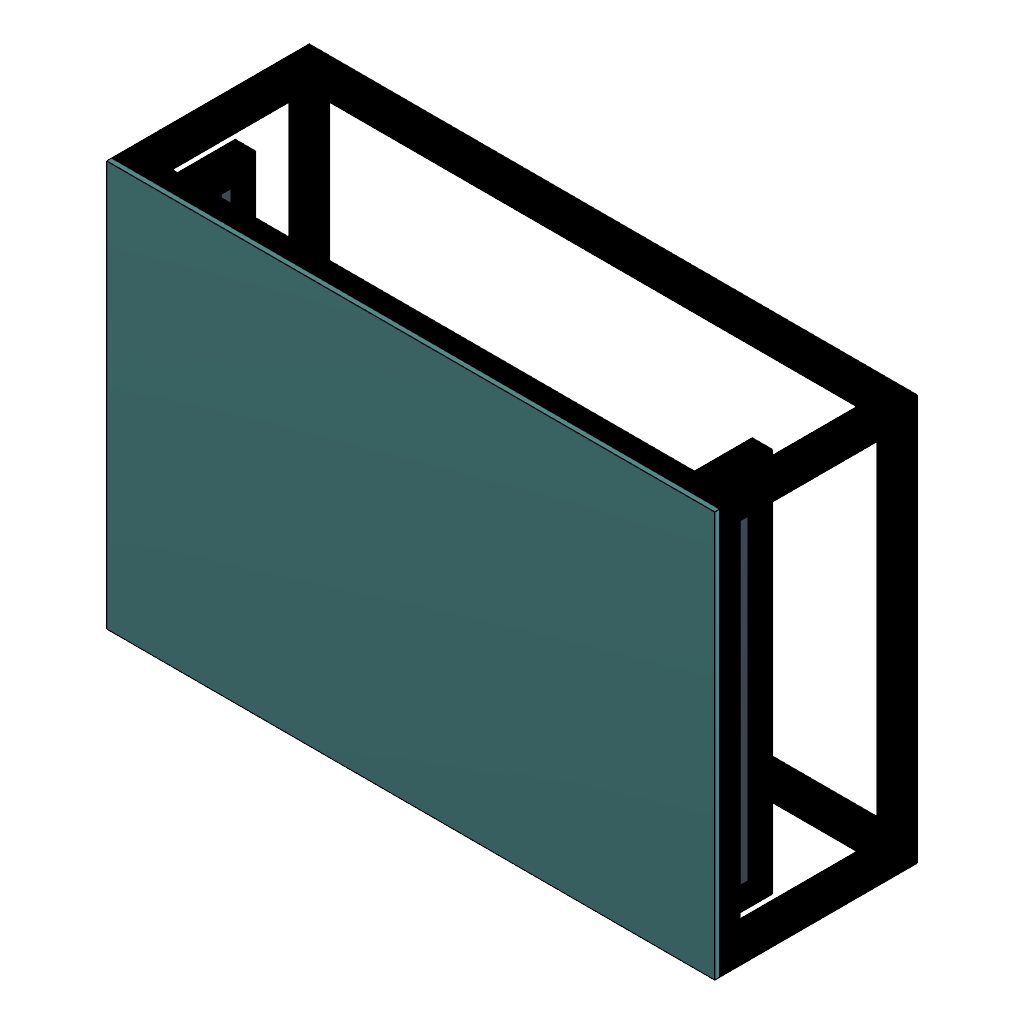
01_frame (Autodesk Fusion 360 design; units mm, degrees)
part number: 2026-11-06-17-38-32-427
part number: 2026-11-06-17-38-33-614
part number: 2026-11-06-17-38-33-635
part number: 2026-11-06-17-38-33-703
part number: 2026-11-06-17-38-33-779
part number: 2026-11-06-17-38-33-883
part number: 2026-11-06-17-38-34-010
part number: 2026-11-06-17-38-34-145
part number: 2026-11-06-17-38-34-299
part number: 2026-11-06-17-38-34-484
part number: 2026-11-06-17-38-34-675
part number: 2026-11-06-17-38-34-881
part number: 2026-11-06-17-38-35-101
part number: 2026-11-06-17-38-35-315
part number: 2026-11-06-17-38-35-617
part number: 2026-11-06-17-38-35-913
part number: 2026-11-06-17-38-36-189
part number: 2026-11-06-17-38-36-471
part number: 2026-11-06-17-38-36-758
part number: 2026-11-06-17-38-37-074
part number: 2026-11-06-17-38-37-402
part number: 2026-11-06-17-38-37-772
part number: 2026-11-06-17-38-38-167
Autodesk Fusion 360 part; units mm, degrees
ref_plane "WorkPlane1" through (0, 0, -25) normal (0, 0, 1) x (1, 0, 0) in component "UpperFront"
sketch "UpperFront footprint" plane through (0, 0, -25) normal (0, 0, 1) x (1, 0, 0) in component "UpperFront"
  line L0 (-300, -200) -> (300, -200)
  line L1 (300, -200) -> (300, -180)
  line L2 (300, -180) -> (-300, -180)
  line L3 (-300, -180) -> (-300, -200)
extrude "UpperFront" add sketch "UpperFront footprint" along normal blind 20 makes body 1 in component "UpperFront"
ref_plane "WorkPlane1" through (0, 0, -25) normal (0, 0, 1) x (1, 0, 0) in component "UpperRear"
sketch "UpperRear footprint" plane through (0, 0, -25) normal (0, 0, 1) x (1, 0, 0) in component "UpperRear"
  line L0 (-300, 180) -> (300, 180)
  line L1 (300, 180) -> (300, 200)
  line L2 (300, 200) -> (-300, 200)
  line L3 (-300, 200) -> (-300, 180)
extrude "UpperRear" add sketch "UpperRear footprint" along normal blind 20 separate body makes body 2 in component "UpperRear"
ref_plane "WorkPlane1" through (0, 0, -25) normal (0, 0, 1) x (1, 0, 0) in component "UpperLeft"
sketch "UpperLeft footprint" plane through (0, 0, -25) normal (0, 0, 1) x (1, 0, 0) in component "UpperLeft"
  line L0 (-300, -180) -> (-280, -180)
  line L1 (-280, -180) -> (-280, 180)
  line L2 (-280, 180) -> (-300, 180)
  line L3 (-300, 180) -> (-300, -180)
extrude "UpperLeft" add sketch "UpperLeft footprint" along normal blind 20 separate body makes body 3 in component "UpperLeft"
ref_plane "WorkPlane1" through (0, 0, -25) normal (0, 0, 1) x (1, 0, 0) in component "UpperRight"
sketch "UpperRight footprint" plane through (0, 0, -25) normal (0, 0, 1) x (1, 0, 0) in component "UpperRight"
  line L0 (280, -180) -> (300, -180)
  line L1 (300, -180) -> (300, 180)
  line L2 (300, 180) -> (280, 180)
  line L3 (280, 180) -> (280, -180)
extrude "UpperRight" add sketch "UpperRight footprint" along normal blind 20 separate body makes body 4 in component "UpperRight"
ref_plane "WorkPlane1" through (0, 0, -200) normal (0, 0, 1) x (1, 0, 0) in component "LowerFront"
sketch "LowerFront footprint" plane through (0, 0, -200) normal (0, 0, 1) x (1, 0, 0) in component "LowerFront"
  line L0 (-300, -200) -> (300, -200)
  line L1 (300, -200) -> (300, -180)
  line L2 (300, -180) -> (-300, -180)
  line L3 (-300, -180) -> (-300, -200)
extrude "LowerFront" add sketch "LowerFront footprint" along normal blind 20 separate body makes body 5 in component "LowerFront"
ref_plane "WorkPlane1" through (0, 0, -200) normal (0, 0, 1) x (1, 0, 0) in component "LowerRear"
sketch "LowerRear footprint" plane through (0, 0, -200) normal (0, 0, 1) x (1, 0, 0) in component "LowerRear"
  line L0 (-300, 180) -> (300, 180)
  line L1 (300, 180) -> (300, 200)
  line L2 (300, 200) -> (-300, 200)
  line L3 (-300, 200) -> (-300, 180)
extrude "LowerRear" add sketch "LowerRear footprint" along normal blind 20 separate body makes body 6 in component "LowerRear"
ref_plane "WorkPlane1" through (0, 0, -200) normal (0, 0, 1) x (1, 0, 0) in component "LowerLeft"
sketch "LowerLeft footprint" plane through (0, 0, -200) normal (0, 0, 1) x (1, 0, 0) in component "LowerLeft"
  line L0 (-300, -180) -> (-280, -180)
  line L1 (-280, -180) -> (-280, 180)
  line L2 (-280, 180) -> (-300, 180)
  line L3 (-300, 180) -> (-300, -180)
extrude "LowerLeft" add sketch "LowerLeft footprint" along normal blind 20 separate body makes body 7 in component "LowerLeft"
ref_plane "WorkPlane1" through (0, 0, -200) normal (0, 0, 1) x (1, 0, 0) in component "LowerRight"
sketch "LowerRight footprint" plane through (0, 0, -200) normal (0, 0, 1) x (1, 0, 0) in component "LowerRight"
  line L0 (280, -180) -> (300, -180)
  line L1 (300, -180) -> (300, 180)
  line L2 (300, 180) -> (280, 180)
  line L3 (280, 180) -> (280, -180)
extrude "LowerRight" add sketch "LowerRight footprint" along normal blind 20 separate body makes body 8 in component "LowerRight"
ref_plane "WorkPlane1" through (0, 0, -180) normal (0, 0, 1) x (1, 0, 0) in component "Leg_0_0"
sketch "Leg_0_0 footprint" plane through (0, 0, -180) normal (0, 0, 1) x (1, 0, 0) in component "Leg_0_0"
  line L0 (-300, -200) -> (-280, -200)
  line L1 (-280, -200) -> (-280, -180)
  line L2 (-280, -180) -> (-300, -180)
  line L3 (-300, -180) -> (-300, -200)
extrude "Leg_0_0" add sketch "Leg_0_0 footprint" along normal blind 155 separate body makes body 9 in component "Leg_0_0"
ref_plane "WorkPlane1" through (0, 0, -180) normal (0, 0, 1) x (1, 0, 0) in component "Leg_0_1"
sketch "Leg_0_1 footprint" plane through (0, 0, -180) normal (0, 0, 1) x (1, 0, 0) in component "Leg_0_1"
  line L0 (-300, 180) -> (-280, 180)
  line L1 (-280, 180) -> (-280, 200)
  line L2 (-280, 200) -> (-300, 200)
  line L3 (-300, 200) -> (-300, 180)
extrude "Leg_0_1" add sketch "Leg_0_1 footprint" along normal blind 155 separate body makes body 10 in component "Leg_0_1"
ref_plane "WorkPlane1" through (0, 0, -180) normal (0, 0, 1) x (1, 0, 0) in component "Leg_1_0"
sketch "Leg_1_0 footprint" plane through (0, 0, -180) normal (0, 0, 1) x (1, 0, 0) in component "Leg_1_0"
  line L0 (280, -200) -> (300, -200)
  line L1 (300, -200) -> (300, -180)
  line L2 (300, -180) -> (280, -180)
  line L3 (280, -180) -> (280, -200)
extrude "Leg_1_0" add sketch "Leg_1_0 footprint" along normal blind 155 separate body makes body 11 in component "Leg_1_0"
ref_plane "WorkPlane1" through (0, 0, -180) normal (0, 0, 1) x (1, 0, 0) in component "Leg_1_1"
sketch "Leg_1_1 footprint" plane through (0, 0, -180) normal (0, 0, 1) x (1, 0, 0) in component "Leg_1_1"
  line L0 (280, 180) -> (300, 180)
  line L1 (300, 180) -> (300, 200)
  line L2 (300, 200) -> (280, 200)
  line L3 (280, 200) -> (280, 180)
extrude "Leg_1_1" add sketch "Leg_1_1 footprint" along normal blind 155 separate body makes body 12 in component "Leg_1_1"
ref_plane "WorkPlane1" through (0, 0, -5) normal (0, 0, 1) x (1, 0, 0) in component "Tabletop"
sketch "Tabletop footprint" plane through (0, 0, -5) normal (0, 0, 1) x (1, 0, 0) in component "Tabletop"
  line L0 (-300, -200) -> (300, -200)
  line L1 (300, -200) -> (300, 200)
  line L2 (300, 200) -> (-300, 200)
  line L3 (-300, 200) -> (-300, -200)
extrude "Tabletop" add sketch "Tabletop footprint" along normal blind 5 separate body makes body 13 in component "Tabletop"
ref_plane "WorkPlane1" through (0, 0, -92) normal (0, 0, 1) x (1, 0, 0) in component "Left_RailSupport"
sketch "Left_RailSupport footprint" plane through (0, 0, -92) normal (0, 0, 1) x (1, 0, 0) in component "Left_RailSupport"
  line L0 (-265, -175) -> (-245, -175)
  line L1 (-245, -175) -> (-245, 175)
  line L2 (-245, 175) -> (-265, 175)
  line L3 (-265, 175) -> (-265, -175)
extrude "Left_RailSupport" add sketch "Left_RailSupport footprint" along normal blind 20 separate body makes body 14 in component "Left_RailSupport"
ref_plane "WorkPlane1" through (0, 0, -92) normal (0, 0, 1) x (1, 0, 0) in component "Left_SupportBracket_-180"
sketch "Left_SupportBracket_-180 footprint" plane through (0, 0, -92) normal (0, 0, 1) x (1, 0, 0) in component "Left_SupportBracket_-180"
  line L0 (-265, -190) -> (-245, -190)
  line L1 (-245, -190) -> (-245, -170)
  line L2 (-245, -170) -> (-265, -170)
  line L3 (-265, -170) -> (-265, -190)
extrude "Left_SupportBracket_-180" add sketch "Left_SupportBracket_-180 footprint" along normal blind 67 separate body makes body 15 in component "Left_SupportBracket_-180"
ref_plane "WorkPlane1" through (0, 0, -92) normal (0, 0, 1) x (1, 0, 0) in component "Left_SupportBracket_180"
sketch "Left_SupportBracket_180 footprint" plane through (0, 0, -92) normal (0, 0, 1) x (1, 0, 0) in component "Left_SupportBracket_180"
  line L0 (-265, 170) -> (-245, 170)
  line L1 (-245, 170) -> (-245, 190)
  line L2 (-245, 190) -> (-265, 190)
  line L3 (-265, 190) -> (-265, 170)
extrude "Left_SupportBracket_180" add sketch "Left_SupportBracket_180 footprint" along normal blind 67 separate body makes body 16 in component "Left_SupportBracket_180"
ref_plane "WorkPlane1" through (0, 0, -72) normal (0, 0, 1) x (1, 0, 0) in component "Left_YRail"
sketch "Left_YRail footprint" plane through (0, 0, -72) normal (0, 0, 1) x (1, 0, 0) in component "Left_YRail"
  line L0 (-261, -175) -> (-249, -175)
  line L1 (-249, -175) -> (-249, 175)
  line L2 (-249, 175) -> (-261, 175)
  line L3 (-261, 175) -> (-261, -175)
extrude "Left_YRail" add sketch "Left_YRail footprint" along normal blind 10 separate body makes body 17 in component "Left_YRail"
ref_plane "WorkPlane1" through (0, 0, -92) normal (0, 0, 1) x (1, 0, 0) in component "Right_RailSupport"
sketch "Right_RailSupport footprint" plane through (0, 0, -92) normal (0, 0, 1) x (1, 0, 0) in component "Right_RailSupport"
  line L0 (245, -175) -> (265, -175)
  line L1 (265, -175) -> (265, 175)
  line L2 (265, 175) -> (245, 175)
  line L3 (245, 175) -> (245, -175)
extrude "Right_RailSupport" add sketch "Right_RailSupport footprint" along normal blind 20 separate body makes body 18 in component "Right_RailSupport"
ref_plane "WorkPlane1" through (0, 0, -92) normal (0, 0, 1) x (1, 0, 0) in component "Right_SupportBracket_-180"
sketch "Right_SupportBracket_-180 footprint" plane through (0, 0, -92) normal (0, 0, 1) x (1, 0, 0) in component "Right_SupportBracket_-180"
  line L0 (245, -190) -> (265, -190)
  line L1 (265, -190) -> (265, -170)
  line L2 (265, -170) -> (245, -170)
  line L3 (245, -170) -> (245, -190)
extrude "Right_SupportBracket_-180" add sketch "Right_SupportBracket_-180 footprint" along normal blind 67 separate body makes body 19 in component "Right_SupportBracket_-180"
ref_plane "WorkPlane1" through (0, 0, -92) normal (0, 0, 1) x (1, 0, 0) in component "Right_SupportBracket_180"
sketch "Right_SupportBracket_180 footprint" plane through (0, 0, -92) normal (0, 0, 1) x (1, 0, 0) in component "Right_SupportBracket_180"
  line L0 (245, 170) -> (265, 170)
  line L1 (265, 170) -> (265, 190)
  line L2 (265, 190) -> (245, 190)
  line L3 (245, 190) -> (245, 170)
extrude "Right_SupportBracket_180" add sketch "Right_SupportBracket_180 footprint" along normal blind 67 separate body makes body 20 in component "Right_SupportBracket_180"
ref_plane "WorkPlane1" through (0, 0, -72) normal (0, 0, 1) x (1, 0, 0) in component "Right_YRail"
sketch "Right_YRail footprint" plane through (0, 0, -72) normal (0, 0, 1) x (1, 0, 0) in component "Right_YRail"
  line L0 (249, -175) -> (261, -175)
  line L1 (261, -175) -> (261, 175)
  line L2 (261, 175) -> (249, 175)
  line L3 (249, 175) -> (249, -175)
extrude "Right_YRail" add sketch "Right_YRail footprint" along normal blind 10 separate body makes body 21 in component "Right_YRail"
component "Frame" placed x (1, 0, 0) y (0, 1, 0) z (0, 0, 1) at (0, 0, 0)
component "UpperFront" placed x (1, 0, 0) y (0, 1, 0) z (0, 0, 1) at (0, 0, 0) in component "Frame"
component "UpperRear" placed x (1, 0, 0) y (0, 1, 0) z (0, 0, 1) at (0, 0, 0) in component "Frame"
component "UpperLeft" placed x (1, 0, 0) y (0, 1, 0) z (0, 0, 1) at (0, 0, 0) in component "Frame"
component "UpperRight" placed x (1, 0, 0) y (0, 1, 0) z (0, 0, 1) at (0, 0, 0) in component "Frame"
component "LowerFront" placed x (1, 0, 0) y (0, 1, 0) z (0, 0, 1) at (0, 0, 0) in component "Frame"
component "LowerRear" placed x (1, 0, 0) y (0, 1, 0) z (0, 0, 1) at (0, 0, 0) in component "Frame"
component "LowerLeft" placed x (1, 0, 0) y (0, 1, 0) z (0, 0, 1) at (0, 0, 0) in component "Frame"
component "LowerRight" placed x (1, 0, 0) y (0, 1, 0) z (0, 0, 1) at (0, 0, 0) in component "Frame"
component "Leg_0_0" placed x (1, 0, 0) y (0, 1, 0) z (0, 0, 1) at (0, 0, 0) in component "Frame"
component "Leg_0_1" placed x (1, 0, 0) y (0, 1, 0) z (0, 0, 1) at (0, 0, 0) in component "Frame"
component "Leg_1_0" placed x (1, 0, 0) y (0, 1, 0) z (0, 0, 1) at (0, 0, 0) in component "Frame"
component "Leg_1_1" placed x (1, 0, 0) y (0, 1, 0) z (0, 0, 1) at (0, 0, 0) in component "Frame"
component "Tabletop" placed x (1, 0, 0) y (0, 1, 0) z (0, 0, 1) at (0, 0, 0) in component "Frame"
component "Left_RailSupport" placed x (1, 0, 0) y (0, 1, 0) z (0, 0, 1) at (0, 0, 0) in component "Frame"
component "Left_SupportBracket_-180" placed x (1, 0, 0) y (0, 1, 0) z (0, 0, 1) at (0, 0, 0) in component "Frame"
component "Left_SupportBracket_180" placed x (1, 0, 0) y (0, 1, 0) z (0, 0, 1) at (0, 0, 0) in component "Frame"
component "Left_YRail" placed x (1, 0, 0) y (0, 1, 0) z (0, 0, 1) at (0, 0, 0) in component "Frame"
component "Right_RailSupport" placed x (1, 0, 0) y (0, 1, 0) z (0, 0, 1) at (0, 0, 0) in component "Frame"
component "Right_SupportBracket_-180" placed x (1, 0, 0) y (0, 1, 0) z (0, 0, 1) at (0, 0, 0) in component "Frame"
component "Right_SupportBracket_180" placed x (1, 0, 0) y (0, 1, 0) z (0, 0, 1) at (0, 0, 0) in component "Frame"
component "Right_YRail" placed x (1, 0, 0) y (0, 1, 0) z (0, 0, 1) at (0, 0, 0) in component "Frame"
equation "table_width_mm = 600.0 mm" comment "Regenerate from config/design.json after changes"
equation "table_depth_mm = 400.0 mm" comment "Regenerate from config/design.json after changes"
equation "table_thickness_mm = 5.0 mm" comment "Regenerate from config/design.json after changes"
equation "table_height_mm = 200.0 mm" comment "Regenerate from config/design.json after changes"
equation "mechanical_extrusion_mm = 20.0 mm" comment "Regenerate from config/design.json after changes"
equation "mechanical_x_travel_mm = 400.0 mm" comment "Regenerate from config/design.json after changes"
equation "mechanical_y_travel_mm = 240.0 mm" comment "Regenerate from config/design.json after changes"
equation "mechanical_x_rail_mm = 500.0 mm" comment "Regenerate from config/design.json after changes"
equation "mechanical_y_rail_mm = 350.0 mm" comment "Regenerate from config/design.json after changes"
equation "mechanical_y_rail_spacing_mm = 510.0 mm" comment "Regenerate from config/design.json after changes"
equation "mechanical_carrier_mm = 75.0 mm" comment "Regenerate from config/design.json after changes"
equation "mechanical_top_clearance_mm = 2.0 mm" comment "Regenerate from config/design.json after changes"
equation "mechanical_sag_tolerance_allowance_mm = 0.5 mm" comment "Regenerate from config/design.json after changes"
equation "mechanical_alignment_tolerance_mm = 2.0 mm" comment "Regenerate from config/design.json after changes"
equation "mechanical_belt_pitch_mm = 2.0 mm" comment "Regenerate from config/design.json after changes"
equation "phone_width_mm = 80.0 mm" comment "Regenerate from config/design.json after changes"
equation "phone_length_mm = 160.0 mm" comment "Regenerate from config/design.json after changes"
equation "phone_thickness_mm = 9.0 mm" comment "Regenerate from config/design.json after changes"
equation "phone_receiver_offset_x_mm = 0.0 mm" comment "Regenerate from config/design.json after changes"
equation "phone_receiver_offset_y_mm = 0.0 mm" comment "Regenerate from config/design.json after changes"
equation "phone_receiver_depth_mm = 1.5 mm" comment "Regenerate from config/design.json after changes"
equation "tx_outer_radius_mm = 25.0 mm" comment "Regenerate from config/design.json after changes"
equation "tx_inner_radius_mm = 10.0 mm" comment "Regenerate from config/design.json after changes"
equation "tx_thickness_mm = 1.2 mm" comment "Regenerate from config/design.json after changes"
equation "tx_strand_diameter_mm = 0.08 mm" comment "Regenerate from config/design.json after changes"
equation "tx_ferrite_radius_mm = 30.0 mm" comment "Regenerate from config/design.json after changes"
equation "tx_ferrite_thickness_mm = 1.0 mm" comment "Regenerate from config/design.json after changes"
equation "rx_outer_radius_mm = 20.0 mm" comment "Regenerate from config/design.json after changes"
equation "rx_inner_radius_mm = 8.0 mm" comment "Regenerate from config/design.json after changes"
equation "rx_thickness_mm = 1.0 mm" comment "Regenerate from config/design.json after changes"
equation "rx_strand_diameter_mm = 0.08 mm" comment "Regenerate from config/design.json after changes"
equation "rx_ferrite_radius_mm = 23.0 mm" comment "Regenerate from config/design.json after changes"
equation "rx_ferrite_thickness_mm = 1.0 mm" comment "Regenerate from config/design.json after changes"
named bodies: "UpperFront", "UpperRear", "UpperLeft", "UpperRight", "LowerFront", "LowerRear", "LowerLeft", "LowerRight", "Leg_0_0", "Leg_0_1", "Leg_1_0", "Leg_1_1", "Tabletop", "Left_RailSupport", "Left_SupportBracket_-180", "Left_SupportBracket_180", "Left_YRail", "Right_RailSupport", "Right_SupportBracket_-180", "Right_SupportBracket_180", "Right_YRail"
